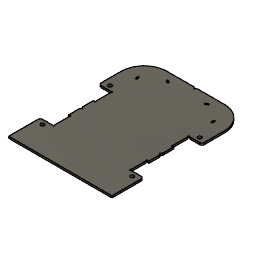
Mice_Sweep (Autodesk Fusion 360 archive; units mm, degrees)
design "下基板"
Autodesk Fusion 360 part; units mm, degrees
sketch "スケッチ1" plane through (0, 0, 0) normal (0, 0, 1) x (1, 0, 0)
  line L0 (-20.044, 48.7765) -> (-21.7923, 49.7477)
  arc A0 (-19.5097, 49.738) -> (-20.044, 48.7765) centre (-19.7768, 49.2572) cw
  arc A1 (-21.7923, 49.7477) -> (-21.2581, 50.7093) centre (-21.5252, 50.2285) cw
  line L1 (-21.2581, 50.7093) -> (-19.5097, 49.738)
  line L2 (31.285, 3.2481) -> (30.335, 3.2481)
  line L3 (-37.765, 3.2481) -> (-38.715, 3.2481)
  arc A2 (-37.215, -32.552) -> (-37.765, -33.102) centre (-37.215, -33.102) cw
  arc A3 (41.285, 37.2481) -> (21.285, 57.2481) centre (21.285, 37.2481) ccw
  line L4 (-38.715, -5.9017) -> (-38.715, -6.7519)
  line L5 (-38.715, 3.2481) -> (-38.715, -5.9017)
  line L6 (-37.765, -33.102) -> (-46.715, -33.102)
  line L7 (31.285, -5.9017) -> (31.285, 3.2481)
  line L8 (-38.715, -6.7519) -> (-37.215, -7.7519)
  arc A4 (29.785, 17.0483) -> (30.335, 17.5983) centre (29.785, 17.5983) cw
  line L9 (-38.715, -18.7519) -> (-37.765, -18.7519)
  line L10 (-37.215, -19.3019) -> (-37.215, -32.552)
  line L11 (29.785, 3.7981) -> (29.785, 17.0483)
  line L12 (-4.715, 57.2481) -> (-28.715, 57.2481)
  line L13 (-3.715, 55.7481) -> (-4.715, 57.2481)
  arc A5 (-46.715, -33.102) -> (-48.715, -35.102) centre (-46.715, -35.102) ccw
  arc A6 (-48.715, 19.5983) -> (-46.715, 17.5983) centre (-46.715, 19.5983) ccw
  line L14 (-48.715, -60.7519) -> (41.285, -60.7519)
  line L15 (-38.715, -8.7519) -> (-38.715, -18.7519)
  line L16 (-48.715, -35.102) -> (-48.715, -40.7519)
  arc A7 (-37.765, 17.5983) -> (-37.215, 17.0483) centre (-37.215, 17.5983) cw
  line L17 (-37.215, -7.7519) -> (-38.715, -8.7519)
  arc A8 (-37.765, -18.7519) -> (-37.215, -19.3019) centre (-37.215, -18.7519) cw
  line L18 (21.285, 57.2481) -> (-2.715, 57.2481)
  line L19 (41.285, -40.7519) -> (41.285, -35.102)
  line L20 (41.285, 19.5983) -> (41.285, 37.2481)
  line L21 (39.285, -33.102) -> (30.335, -33.102)
  arc A9 (39.285, 17.5983) -> (41.285, 19.5983) centre (39.285, 19.5983) ccw
  line L22 (-48.715, -40.7519) -> (-48.715, -60.7519)
  line L23 (31.285, -18.7519) -> (31.285, -8.7519)
  line L24 (-37.215, 17.0483) -> (-37.215, 3.7981)
  line L25 (30.335, 17.5983) -> (39.285, 17.5983)
  line L26 (31.285, -8.7519) -> (29.785, -7.7519)
  line L27 (30.335, -18.7519) -> (31.285, -18.7519)
  line L28 (-46.715, 17.5983) -> (-37.765, 17.5983)
  arc A10 (41.285, -35.102) -> (39.285, -33.102) centre (39.285, -35.102) ccw
  arc A11 (-37.215, 3.7981) -> (-37.765, 3.2481) centre (-37.215, 3.2481) cw
  arc A12 (30.335, 3.2481) -> (29.785, 3.7981) centre (29.785, 3.2481) cw
  arc A13 (30.335, -33.102) -> (29.785, -32.552) centre (29.785, -33.102) cw
  line L29 (41.285, -60.7519) -> (41.285, -40.7519)
  line L30 (29.785, -32.552) -> (29.785, -19.3019)
  line L31 (31.285, -6.7519) -> (31.285, -5.9017)
  line L32 (-48.715, 37.2481) -> (-48.715, 19.5983)
  line L33 (-2.715, 57.2481) -> (-3.715, 55.7481)
  arc A14 (-28.715, 57.2481) -> (-48.715, 37.2481) centre (-28.715, 37.2481) ccw
  line L34 (29.785, -7.7519) -> (31.285, -6.7519)
  arc A15 (29.785, -19.3019) -> (30.335, -18.7519) centre (29.785, -18.7519) cw
  arc A16 (12.6139, 48.7765) -> (12.0797, 49.738) centre (12.3468, 49.2572) cw
  arc A17 (13.828, 50.7093) -> (14.3622, 49.7477) centre (14.0951, 50.2285) cw
  line L35 (12.0797, 49.738) -> (13.828, 50.7093)
  line L36 (14.3622, 49.7477) -> (12.6139, 48.7765)
  arc A18 (-35.9715, 38.427) -> (-37.0548, 38.236) centre (-36.5131, 38.3315) cw
  line L37 (-36.3188, 40.3966) -> (-35.9715, 38.427)
  line L38 (-37.0548, 38.236) -> (-37.4021, 40.2056)
  arc A19 (-37.4021, 40.2056) -> (-36.3188, 40.3966) centre (-36.8604, 40.3011) cw
  line L39 (28.8887, 40.3966) -> (28.5414, 38.427)
  arc A20 (28.5414, 38.427) -> (29.6247, 38.236) centre (29.0831, 38.3315) ccw
  arc A21 (29.972, 40.2056) -> (28.8887, 40.3966) centre (29.4304, 40.3011) ccw
  line L40 (29.6247, 38.236) -> (29.972, 40.2056)
  circle A22 centre (-42.815, 21.5983) radius 1.55
  circle A23 centre (35.385, 21.5983) radius 1.55
  circle A24 centre (35.385, -37.102) radius 1.55
  circle A25 centre (-42.815, -37.102) radius 1.55
  point P0 (-3.715, -7.7519)
  point P1 (-3.715, -7.7519)
extrude "押し出し1" add sketch "スケッチ1" along normal blind 1.6

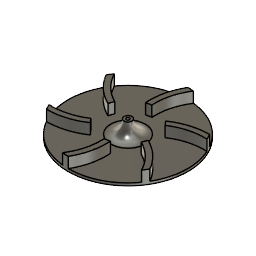
design "吸引ファン1"
Autodesk Fusion 360 part; units mm, degrees
sketch "スケッチ1" plane through (0, 0, 0) normal (0, 0, 1) x (1, 0, 0)
  circle A0 centre (0, 0) radius 22.5
  dimension "d1" = 45
  constraint coincident A0.centre origin
  measures "d1" diameter of A0
extrude "押し出し1" add sketch "スケッチ1" along normal blind 1
sketch "スケッチ2" plane through (0, 0, 1) normal (0, 0, 1) x (-1, 0, 0)
  circle A0 centre (0, 0) radius 22.5
  line L0 (0, 0) -> (0, 22.5)
  line L1 (0, 0) -> (-11.25, 19.4856)
  line L2 (0, 0) -> (-19.4856, 11.25)
  line L3 (0, 0) -> (-22.5, 0)
  line L4 (0, 0) -> (-19.4856, -11.25)
  line L5 (0, 0) -> (-11.25, -19.4856)
  line L6 (0, 0) -> (0, -22.5)
  line L7 (0, 0) -> (11.25, -19.4856)
  line L8 (0, 0) -> (19.4856, -11.25)
  line L9 (0, 0) -> (22.5, 0)
  line L10 (0, 0) -> (19.4856, 11.25)
  line L11 (0, 0) -> (11.25, 19.4856)
  circle A1 centre (0, 22.5) radius 22.5
  circle A2 centre (0, 22.5) radius 20.5
  circle A3 centre (-19.4856, 11.25) radius 20.5
  circle A4 centre (-19.4856, 11.25) radius 22.5
  circle A5 centre (-19.4856, -11.25) radius 20.5
  circle A6 centre (-19.4856, -11.25) radius 22.5
  circle A7 centre (0, -22.5) radius 20.5
  circle A8 centre (0, -22.5) radius 22.5
  circle A9 centre (19.4856, -11.25) radius 20.5
  circle A10 centre (19.4856, -11.25) radius 22.5
  circle A11 centre (19.4856, 11.25) radius 20.5
  circle A12 centre (19.4856, 11.25) radius 22.5
  circle A13 centre (0, 0) radius 10
  dimension "d5" = 360
  dimension "d6" = -2
  dimension "d8" = 360
  constraint coincident A0.centre L0.start
  constraint coincident A0 L0.end
  constraint vertical L0
  constraint coincident L0.end A1.centre
  constraint coincident A0.centre A1
extrude "押し出し2" add sketch "スケッチ2" along normal blind 4 contours A0 A1 A9 | L10 A1 A9 | L10 A2 A10 | L8 A7 A12 | L8 A8 A11 | A0 A7 A12 | A7 A8 A11 A13 | A2 A9 A10 A13 | A0 A4 A11 | L0 A4 A11 | L0 A3 A12 | L6 A5 A10 | L6 A6 A9 | A0 A5 A10 | A5 A6 A9 A13 | A3 A11 A12 A13 | A1 A2 A5 A13 | A3 A4 A7 A13 | A0 A2 A6 | L2 A2 A6 | L2 A1 A5 | A0 A3 A8 | L4 A3 A8 | L4 A4 A7 picked at (14.7277, -6.4258) picked at (12.9288, 9.5417) picked at (1.8397, -15.7623) picked at (-1.799, 15.9675) picked at (-14.7277, 6.4258) picked at (-12.9288, -9.5417)
sketch "スケッチ3" plane through (0, 0, 1) normal (0, 0, 1) x (-1, 0, 0)
  arc A0 (20.5225, 9.2238) -> (8.1325, 5.8192) centre (19.4856, -11.25) ccw
  arc A1 (8.1325, 5.8192) -> (6.7995, 7.3326) centre (0, 0) ccw
  arc A2 (19.4856, 11.25) -> (6.7995, 7.3326) centre (19.4856, -11.25) ccw
  arc A3 (19.4856, 11.25) -> (2.2732, 22.3849) centre (0, 0) ccw
  arc A4 (2.2732, 22.3849) -> (-0.9733, 9.9525) centre (19.4856, 11.25) ccw
  arc A5 (-0.9733, 9.9525) -> (-2.9505, 9.5548) centre (0, 0) ccw
  arc A6 (0, 22.5) -> (-2.9505, 9.5548) centre (19.4856, 11.25) ccw
  arc A7 (0, 22.5) -> (-18.2493, 13.1611) centre (0, 0) ccw
  arc A8 (-18.2493, 13.1611) -> (-9.1058, 4.1333) centre (0, 22.5) ccw
  arc A9 (-9.1058, 4.1333) -> (-9.75, 2.2222) centre (0, 0) ccw
  arc A10 (-19.4856, 11.25) -> (-9.75, 2.2222) centre (0, 22.5) ccw
  arc A11 (-19.4856, 11.25) -> (-20.5225, -9.2238) centre (0, 0) ccw
  arc A12 (-20.5225, -9.2238) -> (-8.1325, -5.8192) centre (-19.4856, 11.25) ccw
  arc A13 (-8.1325, -5.8192) -> (-6.7995, -7.3326) centre (0, 0) ccw
  arc A14 (-19.4856, -11.25) -> (-6.7995, -7.3326) centre (-19.4856, 11.25) ccw
  arc A15 (-19.4856, -11.25) -> (-2.2732, -22.3849) centre (0, 0) ccw
  arc A16 (-2.2732, -22.3849) -> (0.9733, -9.9525) centre (-19.4856, -11.25) ccw
  arc A17 (0.9733, -9.9525) -> (2.9505, -9.5548) centre (0, 0) ccw
  arc A18 (0, -22.5) -> (2.9505, -9.5548) centre (-19.4856, -11.25) ccw
  arc A19 (0, -22.5) -> (18.2493, -13.1611) centre (0, 0) ccw
  arc A20 (18.2493, -13.1611) -> (9.1058, -4.1333) centre (0, -22.5) ccw
  arc A21 (9.1058, -4.1333) -> (9.75, -2.2222) centre (0, 0) ccw
  arc A22 (19.4856, -11.25) -> (9.75, -2.2222) centre (0, -22.5) ccw
  arc A23 (19.4856, -11.25) -> (20.5225, 9.2238) centre (0, 0) ccw
  circle A24 centre (0, 0) radius 1.5
  dimension "d11" = 3
  constraint concentric A1 A24
  measures "d11" diameter of A24
extrude "押し出し3" add sketch "スケッチ3" along normal blind 5 contours A24
sketch "スケッチ4" plane through (0, 0, 6) normal (0, 0, 1) x (-1, 0, 0)
  circle A0 centre (0, 0) radius 1.5
  circle A1 centre (0, 0) radius 0.6
  dimension "d14" = 1.2
  constraint coincident A0.centre A1.centre
  measures "d14" diameter of A1
extrude "押し出し4" cut sketch "スケッチ4" against normal blind 35 contours A1
fillet "フィレット1" radius 5 1 edges at (1.3985, -0.5424, 1)

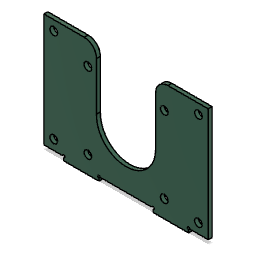
design "モーターマウント"
Autodesk Fusion 360 part; units mm, degrees
sketch "スケッチ1" plane through (0, 0, 0) normal (0, 0, 1) x (1, 0, 0)
  line L0 (25.35, -22.6) -> (25.35, -21)
  line L1 (-11.9915, -0.4526) -> (-11.9915, 20)
  line L2 (12, 0) -> (12, 20)
  arc A0 (-11.9915, 0.4526) -> (8.9572, -7.9855) centre (0, 0) ccw
  arc A1 (8.9572, -7.9855) -> (12, 0) centre (0, 0) ccw
  line L3 (11, -21) -> (-11, -21)
  line L4 (-11, -21) -> (-11, -22.6)
  line L5 (11, -22.6) -> (11, -21)
  line L6 (-25.35, -22.6) -> (-11, -22.6)
  line L7 (11, -22.6) -> (25.35, -22.6)
  line L8 (15.5, 15.5) -> (-15.5, -15.5) construction
  line L9 (-15.5, 15.5) -> (15.5, -15.5) construction
  circle A2 centre (-15.5, 15.5) radius 1.55
  circle A3 centre (-15.5, -15.5) radius 1.55
  circle A4 centre (15.5, -15.5) radius 1.55
  circle A5 centre (15.5, 15.5) radius 1.55
  line L10 (-33.35, 25) -> (-33.35, -21)
  line L11 (-33.35, -21) -> (-25.35, -21)
  line L12 (33.35, 25) -> (33.35, -21)
  line L13 (33.35, -21) -> (25.35, -21)
  line L14 (-33.35, 25) -> (-16.9915, 25)
  line L15 (17, 25) -> (33.35, 25)
  line L16 (-25.35, -21) -> (-25.35, -22.6)
  circle A6 centre (-25.35, -21) radius 0.5
  circle A7 centre (-11, -21) radius 0.5
  circle A8 centre (11, -21) radius 0.5
  circle A9 centre (25.35, -21) radius 0.5
  line L17 (-33.35, 25) -> (-25.35, 25)
  line L18 (-25.35, 25) -> (-25.35, 17)
  line L19 (-33.35, 17) -> (-33.35, 25)
  line L20 (-33.35, -21) -> (-25.35, -21)
  line L21 (-25.35, -21) -> (-25.35, -13)
  line L22 (-33.35, -13) -> (-33.35, -21)
  line L23 (33.35, 25) -> (25.35, 25)
  line L24 (25.35, 25) -> (25.35, 17)
  line L25 (33.35, 17) -> (33.35, 25)
  line L26 (33.35, -21) -> (25.35, -21)
  line L27 (25.35, -21) -> (25.35, -13)
  line L28 (33.35, -13) -> (33.35, -21)
  line L29 (0, 11) -> (0, -6)
  line L30 (-60, 0) -> (-22.7376, 0)
  circle A10 centre (-29.35, 21) radius 1.55
  circle A11 centre (29.35, 21) radius 1.55
  circle A12 centre (-29.35, -17.0232) radius 1.55
  circle A13 centre (29.35, -17.0232) radius 1.55
  arc A14 (-11.9915, 20) -> (-16.9915, 25) centre (-16.9915, 20) ccw
  arc A15 (17, 25) -> (12, 20) centre (17, 20) ccw
  point P0 (82.8077, 25)
  dimension "d5" = 24
  dimension "d11" = 31
  dimension "d12" = 31
  dimension "d13" = 3.1
  dimension "d14" = 3.1
  dimension "d15" = 3.1
  dimension "d16" = 3.1
  dimension "d25" = 14.35
  dimension "d43" = 11
  dimension "d44" = 11
  dimension "d45" = 22.6
  dimension "d46" = 21
  dimension "d49" = 22.6
  dimension "d51" = 33.35
  dimension "d52" = 33.35
  dimension "d53" = 1
  dimension "d54" = 1
  dimension "d55" = 1
  dimension "d56" = 1
  dimension "d57" = 8
  dimension "d58" = 8
  dimension "d59" = 8
  dimension "d60" = 8
  dimension "d61" = 8
  dimension "d62" = 8
  dimension "d63" = 8
  dimension "d64" = 8
  dimension "d83" = 3.1
  dimension "d84" = 3.1
  dimension "d85" = 3.1
  dimension "d86" = 3.1
  dimension "d87" = 14.35
  dimension "d88" = 5
  dimension "d89" = 5
  constraint coincident A0.centre A1.centre
  constraint coincident L1.start A0
  constraint tangent L2 A0
  constraint coincident L1 A0.start
  constraint concentric A0 A1
  constraint perpendicular L3 L4
  constraint parallel L4 L5
  constraint horizontal L3
  constraint coincident L8 A0.centre
  constraint coincident L9 A0.centre
  constraint coincident L9.start A2.centre
  constraint coincident L8.end A3.centre
  constraint coincident L9.end A4.centre
  constraint coincident L8.start A5.centre
  constraint perpendicular L3 L10
  constraint collinear L14 L15
  constraint perpendicular L6 L16
  constraint coincident L11.end L16.start
  constraint coincident L3.end L4.start
  constraint coincident L3.start L5.end
  constraint coincident L0.end L13.end
  constraint horizontal L17
  constraint vertical L18
  constraint vertical L19
  constraint horizontal L20
  constraint vertical L21
  constraint vertical L22
  constraint horizontal L23
  constraint vertical L24
  constraint vertical L25
  constraint horizontal L26
  constraint vertical L27
  constraint vertical L28
  constraint vertical L29
  constraint horizontal L30
  constraint tangent L14 A14
  constraint tangent L1 A14
  constraint tangent L15 A15
  constraint tangent L2 A15
  measures "d5" diameter of A0
  measures "d11" distance of L8.end L9.end
  measures "d12" distance of L9.start L8.end
  measures "d13" diameter of A2
  measures "d14" diameter of A3
  measures "d15" diameter of A4
  measures "d16" diameter of A5
  measures "d25" distance of L0 L5
  measures "d43" distance of A0.centre L4
  measures "d44" distance of L5 A0.centre
  measures "d45" distance of A0.centre L6
  measures "d46" distance of A0.centre L3
  measures "d49" distance of A0.centre L7
  measures "d51" distance of A0.centre L10
  measures "d52" distance of A0.centre L12
  measures "d53" diameter of A6
  measures "d54" diameter of A7
  measures "d55" diameter of A8
  measures "d56" diameter of A9
  measures "d57" distance of L10.start L17.end
  measures "d58" distance of L10.start L19.start
  measures "d59" distance of L10.end L11.end
  measures "d60" distance of L10.end L22.start
  measures "d61" distance of L12.start L23.end
  measures "d62" distance of L12.start L25.start
  measures "d63" distance of L12.end L0.end
  measures "d64" distance of L12.end L28.start
  measures "d83" diameter of A10
  measures "d84" diameter of A11
  measures "d85" diameter of A12
  measures "d86" diameter of A13
  measures "d87" distance of L6.start L4
  measures "d88" radius of A14
  measures "d89" radius of A15
extrude "押し出し1" add sketch "スケッチ1" along normal blind 1.57 contours L0 L1 L2 A0 A1 L3 L4 L5 L6 L7 L10 L11 L12 L13 L14 L15 L16 A6 A7 A8 A9 L17 L19 L20 L22 L23 L25 L26 L28 A14 A15 sketch seen with x (1, 0, 0) y (0, 1, 0) z (0, 0, 1) at (33.35, 22.6, 0) in component "ボード"
component "ボード" placed x (1, 0, 0) y (0, 1, 0) z (0, 0, 1) at (-33.35, -22.6, 0)
equation "d45 = 21 mm + 1.6 mm"
equation "d51 = ( 50.7 / 2 + 8 ) * 1 mm"
equation "d52 = ( 50.7 / 2 + 8 ) * 1 mm"
named bodies: "ボード"

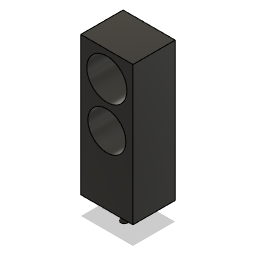
design "センサーホルダー"
Autodesk Fusion 360 part; units mm, degrees
sketch "スケッチ2" plane through (0, 0, 0) normal (0, 0, 1) x (1, 0, 0)
  line L0 (0, 10) -> (0, -10) construction
  line L1 (-10, 0) -> (10, 0) construction
  circle A0 centre (0, 0) radius 2.7
  circle A1 centre (0, 6.35) radius 2.85
  line L2 (0, 10) -> (-3.7, 10)
  line L3 (-3.7, 10) -> (-3.7, -9.7)
  line L4 (-3.7, -9.7) -> (0, -9.7)
  line L5 (0, 10) -> (3.7, 10)
  line L6 (3.7, 10) -> (3.7, -9.7)
  line L7 (3.7, -9.7) -> (0, -9.7)
  dimension "d5" = 20
  dimension "d6" = 20
  dimension "d7" = 5.4
  dimension "d8" = 5.7
  dimension "d9" = 6.35
  dimension "d10" = 3.7
  dimension "d11" = 3.65
  dimension "d12" = 19.7
  constraint vertical L0
  constraint perpendicular L0 L1
  constraint coincident A0.centre origin
  constraint coincident L0 A1.centre
  constraint horizontal L2
  constraint perpendicular L2 L3
  constraint coincident L0 L4.end
  constraint perpendicular L0 L4
  constraint symmetric L0 L2.start L5.start
  constraint symmetric L0 L2.end L5.end
  constraint symmetric L0 L3.end L6.end
  constraint symmetric L0 L4.end L7.end
  measures "d5" distance of L0.start L0.end
  measures "d6" distance of L1.start L1.end
  measures "d7" diameter of A0
  measures "d8" diameter of A1
  measures "d9" distance of A0.centre A1.centre
  measures "d10" distance of L0.start L2.end
  measures "d11" distance of A1.centre L2
  measures "d12" distance of L2.end L3.end
extrude "押し出し2" add sketch "スケッチ2" along normal blind 5 and the other way blind 1
sketch "スケッチ3" plane through (0, -9.7, 0) normal (0, -1, 0) x (1, 0, 0)
  line L0 (-3.7, -1) -> (3.7, -1)
  line L1 (3.7, -1) -> (3.7, 5)
  line L2 (3.7, 5) -> (-3.7, 5)
  line L3 (-3.7, 5) -> (-3.7, -1)
  line L4 (0, 0) -> (0, 3.1) construction
  line L5 (1.0608, 2.55) -> (-1.3, 2.55) construction
  line L6 (1.116, 0.55) -> (-1.3, 0.55) construction
  line L7 (-0.55, 2.55) -> (-0.55, 0.55)
  line L8 (0.55, 0.55) -> (0.55, 2.55)
  arc A0 (0.55, 2.55) -> (-0.55, 2.55) centre (0, 2.55) ccw
  arc A1 (-0.55, 0.55) -> (0.55, 0.55) centre (0, 0.55) ccw
  dimension "d15" = 3.1
  dimension "d24" = 1.1
  constraint coincident L4.start origin
  constraint perpendicular L0 L4
  constraint horizontal L5
  constraint perpendicular L4 L6
  constraint coincident L6 A1.centre
  constraint coincident L4 A1.centre
  constraint coincident L4.start A1
  constraint coincident L5 A0.centre
  constraint coincident L4 A0.centre
  constraint coincident L4.end A0
  constraint coincident L5 L7.start
  constraint coincident L6 L7.end
  constraint coincident L6 L8.start
  constraint coincident L5 L8.end
  measures "d15" distance of L4.start L4.end
  measures "d24" distance of L7 L8
extrude "押し出し3" add sketch "スケッチ3" along normal blind 2.6 contours L7 L8 A0 A1
move_face "面をオフセット1" offset -0.08 1 faces at (0.55, -11.4333, 1.8833)
equation "d9 = ( 5.7 / 2 ) * 1 mm + ( 5.4 / 2 ) * 1 mm + 0.8 mm"
equation "d11 = ( 5.7 / 2 ) * 1 mm + 0.8 mm"
equation "d12 = 0.8 mm + 5.7 mm + 0.8 mm + 5.4 mm + 7 mm"
equation "d15 = 1.1 mm + 2 mm"

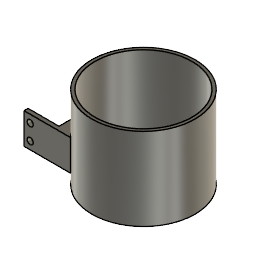
design "吸引筒"
Autodesk Fusion 360 part; units mm, degrees
sketch "スケッチ1" plane through (0, 0, 0) normal (0, 0, 1) x (1, 0, 0)
  circle A0 centre (0, 0) radius 25
  circle A1 centre (0, 0) radius 23.5
  dimension "d1" = 50
  dimension "d2" = 47
  constraint coincident A0.centre A1.centre
  constraint concentric A0 A1
  measures "d1" diameter of A0
  measures "d2" diameter of A1
extrude "押し出し1" add sketch "スケッチ1" along normal blind 40
sketch "スケッチ2" plane through (0, 0, 0) normal (0, 0, -1) x (1, 0, 0)
  circle A0 centre (0, 0) radius 23.5
  circle A1 centre (0, 0) radius 25
  line L0 (0, 0) -> (25, 0)
  line L1 (0, 0) -> (-25, 0)
  line L2 (0, 0) -> (0, -25)
  line L3 (0, 0) -> (0, 25)
  line L4 (-4, 0) -> (-4, -25)
  line L5 (4, 0) -> (4, -25)
  line L6 (0, 4) -> (-25, 4)
  line L7 (0, -4) -> (-25, -4)
  line L8 (4, 0) -> (4, 25)
  line L9 (-4, 0) -> (-4, 25)
  line L10 (0, -4) -> (25, -4)
  line L11 (0, 4) -> (25, 4)
  dimension "d5" = 4
  dimension "d6" = -4
  dimension "d7" = 4
  dimension "d8" = -4
  dimension "d9" = 4
  dimension "d10" = -4
  dimension "d11" = 4
  dimension "d12" = -4
  constraint coincident A0.centre A1.centre
  constraint coincident A1 L0.end
  constraint horizontal L0
  constraint coincident A1 L1.end
  constraint parallel L0 L1
  constraint coincident A1 L2.end
  constraint perpendicular L0 L2
  constraint coincident A1 L3.end
  constraint perpendicular L0 L3
extrude "押し出し2" add sketch "スケッチ2" against normal blind 8 contours A0 L0 L8 L11 | A0 L0 L5 L10 | L0 L2 L5 L10 | L0 L3 L8 L11 | A0 L3 L8 L11 | A0 L2 L5 L10 | L1 L2 L4 L7 | L1 L3 L6 L9 | A0 L3 L6 L9 | A0 L2 L4 L7 | A0 L1 L4 L7 | A0 L1 L6 L9
sketch "スケッチ3" plane through (0, 0, 0) normal (0, 0, -1) x (1, 0, 0)
  arc A0 (23.1571, 4) -> (4, 23.1571) centre (0, 0) ccw
  line L0 (23.1571, 4) -> (4, 4)
  line L1 (4, 4) -> (4, 23.1571)
  line L2 (-4, 23.1571) -> (-4, 4)
  line L3 (-4, 4) -> (-23.1571, 4)
  arc A1 (-4, 23.1571) -> (-23.1571, 4) centre (0, 0) ccw
  line L4 (-23.1571, -4) -> (-4, -4)
  line L5 (-4, -4) -> (-4, -23.1571)
  arc A2 (-23.1571, -4) -> (-4, -23.1571) centre (0, 0) ccw
  line L6 (4, -23.1571) -> (4, -4)
  line L7 (4, -4) -> (23.1571, -4)
  arc A3 (4, -23.1571) -> (23.1571, -4) centre (0, 0) ccw
  circle A4 centre (0, 0) radius 25
  circle A5 centre (0, 0) radius 23.5
  constraint concentric A0 A5
  constraint coincident L4.start A5
extrude "押し出し3" cut sketch "スケッチ3" against normal blind 5 contours L0 L1 L2 L3 L4 L5 L6 L7 A5
sketch "スケッチ4" plane through (0, 0, 8) normal (0, 0, 1) x (-1, 0, 0)
  arc A0 (-23.1571, 4) -> (-23.1571, -4) centre (0, 0) ccw
  line L0 (-23.1571, -4) -> (-4, -4)
  line L1 (-4, -4) -> (-4, -23.1571)
  arc A1 (-4, -23.1571) -> (4, -23.1571) centre (0, 0) ccw
  line L2 (4, -23.1571) -> (4, -4)
  line L3 (4, -4) -> (23.1571, -4)
  arc A2 (23.1571, -4) -> (23.1571, 4) centre (0, 0) ccw
  line L4 (23.1571, 4) -> (4, 4)
  line L5 (4, 4) -> (4, 23.1571)
  arc A3 (4, 23.1571) -> (-4, 23.1571) centre (0, 0) ccw
  line L6 (-4, 23.1571) -> (-4, 4)
  line L7 (-4, 4) -> (-23.1571, 4)
sketch "スケッチ5" plane through (0, 0, 8) normal (0, 0, 1) x (-1, 0, 0)
  circle A0 centre (0, 0) radius 4.25
  circle A1 centre (0, 0) radius 8.5
  dimension "d17" = 8.5
  dimension "d20" = 17
  constraint coincident A0.centre A1.centre
  constraint concentric A0 A1
  measures "d17" diameter of A0
  measures "d20" diameter of A1
extrude "押し出し4" add sketch "スケッチ5" against normal blind 3
sketch "スケッチ6" plane through (0, 0, 8) normal (0, 0, 1) x (-1, 0, 0)
  circle A0 centre (0, 0) radius 4.35
  circle A1 centre (0, 0) radius 5.75
  dimension "d21" = 8.7
  dimension "d22" = 11.5
  constraint coincident A0.centre A1.centre
  measures "d21" diameter of A0
  measures "d22" diameter of A1
extrude "押し出し5" add sketch "スケッチ6" along normal blind 11
fillet "フィレット1" radius 3 1 edges at (5.3609, -2.0793, 8)
sketch "スケッチ7" plane through (0, 0, 8) normal (0, 0, 1) x (-1, 0, 0)
  circle A0 centre (0, 0) radius 4.35
  circle A1 centre (0, 0) radius 3
  constraint coincident A0.centre A1.centre
extrude "押し出し6" cut sketch "スケッチ7" against normal blind 19 contours A1
extrude "押し出し7" cut 1 faces at (-3.8838, 0.2161, 8) along direction (0, 0, -1) blind 2
extrude "押し出し8" cut 1 faces at (-5.2457, 0.5018, 19) along direction (0, 0, -1) blind 5
sketch "スケッチ8" plane through (0, 0, 5) normal (0, 0, -1) x (1, 0, 0)
  circle A0 centre (0, 0) radius 3
  line L0 (-4, -7.5) -> (-4, -23.1571)
  arc A1 (-4, -23.1571) -> (4, -23.1571) centre (0, 0) ccw
  line L1 (4, -23.1571) -> (4, -7.5)
  arc A2 (4, -7.5) -> (7.5, -4) centre (0, 0) ccw
  line L2 (7.5, -4) -> (23.1571, -4)
  arc A3 (23.1571, -4) -> (23.1571, 4) centre (0, 0) ccw
  line L3 (23.1571, 4) -> (7.5, 4)
  arc A4 (7.5, 4) -> (4, 7.5) centre (0, 0) ccw
  line L4 (4, 7.5) -> (4, 23.1571)
  arc A5 (4, 23.1571) -> (-4, 23.1571) centre (0, 0) ccw
  line L5 (-4, 23.1571) -> (-4, 7.5)
  arc A6 (-4, 7.5) -> (-7.5, 4) centre (0, 0) ccw
  line L6 (-7.5, 4) -> (-23.1571, 4)
  arc A7 (-23.1571, 4) -> (-23.1571, -4) centre (0, 0) ccw
  line L7 (-23.1571, -4) -> (-7.5, -4)
  arc A8 (-7.5, -4) -> (-4, -7.5) centre (0, 0) ccw
  line L8 (0, 0) -> (-25, 0)
  line L9 (-25, 0) -> (-25, 15.95)
  circle A9 centre (0, 0) radius 25
  line L10 (-25, 15.95) -> (-19.2509, 15.95)
  line L11 (-25, 15.95) -> (-40, 15.95)
  line L12 (-40, 15.95) -> (-40, 17.95)
  line L13 (-40, 17.95) -> (-17.4011, 17.95)
  line L14 (-25, 0) -> (-25, -15.95)
  line L15 (-25, -15.95) -> (-40, -15.95)
  line L16 (-40, -17.95) -> (-17.4011, -17.95)
  line L17 (-25, -15.95) -> (-19.2509, -15.95)
  line L18 (-40, -15.95) -> (-40, -17.95)
  point P0 (-23.1571, -4)
  dimension "d33" = 15.95
  dimension "d34" = 2
  constraint coincident A0.centre A1.centre
  constraint horizontal L8
  constraint perpendicular L8 L9
  constraint concentric A0 A9
  constraint coincident L8.end A9
  constraint coincident A9 L10.end
  constraint perpendicular L9 L10
  constraint perpendicular L9 L11
  constraint perpendicular L11 L12
  constraint coincident A9 L13.end
  constraint perpendicular L12 L13
  constraint symmetric L6.end L8 P0
  constraint symmetric L9.start L8 L14.start
  constraint symmetric L8 L9.end L14.end
  constraint symmetric L8 L10.end L17.end
  constraint symmetric L8 L11.end L15.end
  constraint symmetric L8 L12.end L16.start
  constraint symmetric L8 L13.end L16.end
  measures "d33" distance of L8.end L9.end
  measures "d34" distance of L11.end L12.end
extrude "押し出し9" add sketch "スケッチ8" against normal blind 15 contours L9 A9 L10 | A9 L14 L17 | A9 L10 L11 L12 L13 | A9 L15 L16 L17 L18
sketch "スケッチ9" plane through (0, 17.95, 0) normal (0, 1, 0) x (-1, 0, 0)
  line L0 (17.4011, 5) -> (40, 5)
  line L1 (40, 5) -> (40, 20)
  line L2 (40, 20) -> (17.4011, 20)
  line L3 (17.4011, 20) -> (17.4011, 5)
  line L4 (40, 5) -> (40, 20)
  line L5 (40, 12.5) -> (37, 12.5)
  line L6 (37, 12.5) -> (37, 5)
  circle A0 centre (37, 8.75) radius 1.5
  line L7 (37, 12.5) -> (37, 20)
  circle A1 centre (37, 16.25) radius 1.5
  dimension "d37" = 3
  dimension "d38" = 3
  constraint coincident L0.end L1.start
  constraint coincident L1.end L2.start
  constraint midpoint L1 L5.start
  constraint perpendicular L1 L5
  constraint coincident L0 L6.end
  constraint perpendicular L0 L6
  constraint midpoint L6 A0.centre
  constraint coincident L2 L7.end
  constraint perpendicular L2 L7
  constraint midpoint L7 A1.centre
  measures "d37" diameter of A0
  measures "d38" diameter of A1
extrude "押し出し10" cut sketch "スケッチ9" against normal blind 52 contours L6 A0 | L6 A0 | L7 A1 | L7 A1
equation "d6 = -d5"
equation "d8 = -d7"
equation "d10 = -d9"
equation "d12 = -d11"
equation "d21 = 8.5 mm + 0.2 mm"
equation "d33 = ( 27.9 / 2 ) * 1 mm + 2 mm"

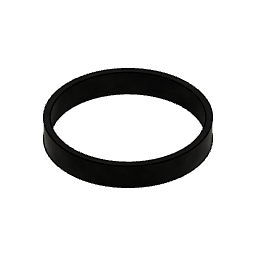
design "タイヤ"
Autodesk Fusion 360 part; units mm, degrees
sketch "スケッチ1" plane through (0, 0, 0) normal (0, 1, 0) x (1, 0, 0)
  circle A0 centre (0, 0) radius 24
  circle A1 centre (0, 0) radius 26
  dimension "d1" = 48
  dimension "d2" = 52
  constraint coincident A0.centre A1.centre
  measures "d1" diameter of A0
  measures "d2" diameter of A1
extrude "押し出し1" add sketch "スケッチ1" along normal blind 8
equation "d2 = 48 mm + 4 mm"

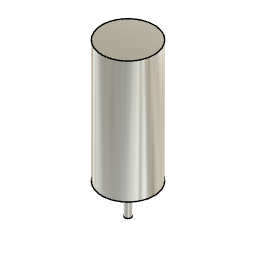
design "吸引モータ"
Autodesk Fusion 360 part; units mm, degrees
sketch "スケッチ1" plane through (0, 0, 0) normal (0, 0, 1) x (1, 0, 0)
  circle A0 centre (0, 0) radius 4.25
  dimension "d1" = 8.5
  constraint coincident A0.centre origin
  measures "d1" diameter of A0
extrude "押し出し1" add sketch "スケッチ1" along normal blind 20
sketch "スケッチ2" plane through (0, 0, 0) normal (0, 0, -1) x (1, 0, 0)
  circle A0 centre (0, 0) radius 4.25
  circle A1 centre (0, 0) radius 0.5
  dimension "d4" = 1
  constraint coincident A0.centre A1.centre
  measures "d4" diameter of A1
extrude "押し出し2" add sketch "スケッチ2" along normal blind 5 contours A1

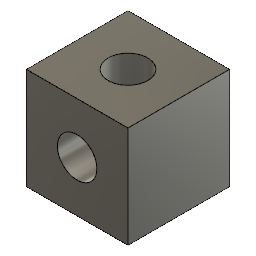
design "角型スペーサ"
Autodesk Fusion 360 part; units mm, degrees
sketch "スケッチ1" plane through (0, 0, 0) normal (0, 0, 1) x (1, 0, 0)
  line L0 (0, 0) -> (8, 0)
  line L1 (8, 0) -> (8, 8)
  line L2 (8, 8) -> (0, 8)
  line L3 (0, 8) -> (0, 0)
  circle A0 centre (4, 4) radius 1.55
  dimension "d1" = 8
  dimension "d4" = 3.1
  constraint horizontal L0
  constraint vertical L1
  constraint horizontal L2
  constraint vertical L3
  constraint coincident L0.start L3.end
  measures "d1" distance of L0.start L2.end
  measures "d4" diameter of A0
extrude "押し出し1" add sketch "スケッチ1" along normal blind 8
sketch "スケッチ2" plane through (0, 0, 0) normal (0, -1, 0) x (1, 0, 0)
  line L0 (0, 0) -> (8, 0)
  line L1 (8, 0) -> (8, 8)
  line L2 (8, 8) -> (0, 8)
  line L3 (0, 8) -> (0, 0)
  circle A0 centre (4, 4) radius 1.55
  dimension "d5" = 3.1
  measures "d5" diameter of A0
extrude "押し出し2" cut sketch "スケッチ2" against normal blind 9 contours A0

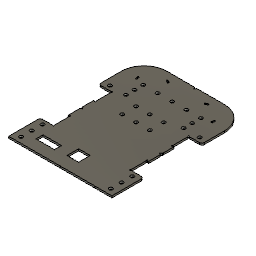
design "上基盤改"
Autodesk Fusion 360 part; units mm, degrees
sketch "スケッチ1" plane through (0, 0, 0) normal (0, 0, 1) x (1, 0, 0)
  line L0 (-16.3289, 51.5283) -> (-18.0773, 52.4996)
  line L1 (-17.543, 53.4612) -> (-15.7947, 52.4899)
  arc A0 (-15.7947, 52.4899) -> (-16.3289, 51.5283) centre (-16.0618, 52.0091) cw
  arc A1 (-18.0773, 52.4996) -> (-17.543, 53.4612) centre (-17.8101, 52.9804) cw
  line L2 (-33.5, 19.8002) -> (-33.5, 6.55)
  arc A2 (33.5, 19.8002) -> (34.05, 20.3502) centre (33.5, 20.3502) cw
  line L3 (34.05, 20.3502) -> (43, 20.3502)
  line L4 (-35, -16) -> (-34.05, -16)
  line L5 (-1, 60) -> (-25, 60)
  line L6 (1, 60) -> (0, 58.5)
  line L7 (25, 60) -> (1, 60)
  line L8 (-43, 20.3502) -> (-34.05, 20.3502)
  arc A3 (45, 40) -> (25, 60) centre (25, 40) ccw
  line L9 (-34.05, 6) -> (-35, 6)
  arc A4 (-33.5, 6.55) -> (-34.05, 6) centre (-33.5, 6) cw
  line L10 (-35, -6) -> (-35, -16)
  arc A5 (-34.05, -16) -> (-33.5, -16.55) centre (-33.5, -16) cw
  arc A6 (-34.05, 20.3502) -> (-33.5, 19.8002) centre (-33.5, 20.3502) cw
  line L11 (45, 22.3502) -> (45, 40)
  line L12 (-45, 40) -> (-45, 22.3502)
  line L13 (-35, -4) -> (-33.5, -5)
  line L14 (0, 58.5) -> (-1, 60)
  line L15 (-35, 6) -> (-35, -3.1498)
  line L16 (-33.5, -5) -> (-35, -6)
  arc A7 (43, 20.3502) -> (45, 22.3502) centre (43, 22.3502) ccw
  arc A8 (-25, 60) -> (-45, 40) centre (-25, 40) ccw
  line L17 (-33.5, -16.55) -> (-33.5, -29.8002)
  line L18 (-45, -32.3502) -> (-45, -38)
  line L19 (-45, -58) -> (45, -58)
  arc A9 (-45, 22.3502) -> (-43, 20.3502) centre (-43, 22.3502) ccw
  line L20 (-34.05, -30.3502) -> (-43, -30.3502)
  arc A10 (-33.5, -29.8002) -> (-34.05, -30.3502) centre (-33.5, -30.3502) cw
  line L21 (-45, -38) -> (-45, -58)
  arc A11 (-43, -30.3502) -> (-45, -32.3502) centre (-43, -32.3502) ccw
  line L22 (45, -58) -> (45, -38)
  line L23 (45, -38) -> (45, -32.3502)
  arc A12 (45, -32.3502) -> (43, -30.3502) centre (43, -32.3502) ccw
  line L24 (43, -30.3502) -> (34.05, -30.3502)
  arc A13 (34.05, -30.3502) -> (33.5, -29.8002) centre (33.5, -30.3502) cw
  line L25 (33.5, -29.8002) -> (33.5, -16.55)
  arc A14 (33.5, -16.55) -> (34.05, -16) centre (33.5, -16) cw
  line L26 (34.05, -16) -> (35, -16)
  line L27 (35, -16) -> (35, -6)
  line L28 (35, -6) -> (33.5, -5)
  line L29 (33.5, -5) -> (35, -4)
  line L30 (35, -4) -> (35, -3.1498)
  line L31 (35, -3.1498) -> (35, 6)
  line L32 (35, 6) -> (34.05, 6)
  arc A15 (34.05, 6) -> (33.5, 6.55) centre (33.5, 6) cw
  line L33 (33.5, 6.55) -> (33.5, 19.8002)
  line L34 (-35, -3.1498) -> (-35, -4)
  arc A16 (16.3289, 51.5283) -> (15.7947, 52.4899) centre (16.0618, 52.0091) cw
  line L35 (15.7947, 52.4899) -> (17.543, 53.4612)
  arc A17 (17.543, 53.4612) -> (18.0773, 52.4996) centre (17.8101, 52.9804) cw
  line L36 (18.0773, 52.4996) -> (16.3289, 51.5283)
  arc A18 (-32.2565, 41.1789) -> (-33.3397, 40.9879) centre (-32.7981, 41.0834) cw
  line L37 (-33.3397, 40.9879) -> (-33.687, 42.9575)
  arc A19 (-33.687, 42.9575) -> (-32.6037, 43.1485) centre (-33.1454, 43.053) cw
  line L38 (-32.6037, 43.1485) -> (-32.2565, 41.1789)
  line L39 (32.6037, 43.1485) -> (32.2565, 41.1789)
  arc A20 (32.2565, 41.1789) -> (33.3397, 40.9879) centre (32.7981, 41.0834) ccw
  line L40 (33.3397, 40.9879) -> (33.687, 42.9575)
  arc A21 (33.687, 42.9575) -> (32.6037, 43.1485) centre (33.1454, 43.053) ccw
  circle A22 centre (-39.1, 24.3502) radius 1.55
  circle A23 centre (39.1, 24.3502) radius 1.55
  circle A24 centre (39.1, -34.3502) radius 1.55
  circle A25 centre (-39.1, -34.3502) radius 1.55
  line L41 (0, -47) -> (5, -47)
  line L42 (0, -47) -> (-5, -47)
  line L43 (-5, -47) -> (-5, -37)
  line L44 (-5, -37) -> (0, -37)
  line L45 (5, -37) -> (0, -37)
  line L46 (5, -47) -> (5, -37)
  line L47 (0, -47) -> (5, -47)
  circle A26 centre (-12, 20) radius 1.5
  circle A27 centre (-12, 8) radius 1.5
  circle A28 centre (12, 20) radius 1.5
  circle A29 centre (12, 8) radius 1.5
  circle A30 centre (0, 20) radius 1.5
  circle A31 centre (0, 8) radius 1.5
  line L48 (-39.1, -34.3502) -> (-39.1, -58)
  line L49 (-39.1, -58) -> (-39.1, -53)
  circle A32 centre (-39.1, -53) radius 1.55
  line L50 (-39.1, -34.3502) -> (-39.1, -43.6752)
  circle A33 centre (-39.1, -43.6752) radius 1.55
  circle A34 centre (39.1, -34.3502) radius 1.55
  circle A35 centre (39.1, -43.6752) radius 1.55
  circle A36 centre (39.1, -53) radius 1.55
  line L51 (0, -58) -> (-30, -58)
  line L52 (0, -58) -> (30, -58)
  line L53 (0, -58) -> (30, -58)
  line L54 (0, -5) -> (-30, -5)
  line L55 (0, -5) -> (30, -5)
  line L56 (-30, -5) -> (-30, -35)
  line L57 (-30, -35) -> (30, -35)
  line L58 (30, -35) -> (30, -5)
  line L59 (-5, -42) -> (-15, -42)
  line L60 (-15, -42) -> (-15, -48)
  line L61 (-15, -48) -> (-25, -48)
  line L62 (-25, -48) -> (-31, -48)
  line L63 (-15, -42) -> (-31, -42)
  line L64 (-31, -42) -> (-31, -48)
  line L65 (39.1, 24.3502) -> (25.1, 24.3502)
  circle A37 centre (25.1, 24.3502) radius 1.5
  line L66 (25.1, 24.3502) -> (25.1, 39.3502)
  circle A38 centre (25.1, 39.3502) radius 1.5
  circle A39 centre (25.1, 31.8502) radius 1.5
  line L67 (25.1, 39.3502) -> (0, 39.3502)
  circle A40 centre (12.55, 39.3502) radius 1.5
  circle A41 centre (0, 39.3502) radius 1.5
  line L68 (0, 58.5) -> (0, 39.3502)
  circle A42 centre (0, 39.3502) radius 1.5
  circle A43 centre (-12.55, 39.3502) radius 1.5
  circle A44 centre (-25.1, 39.3502) radius 1.5
  circle A45 centre (-25.1, 31.8502) radius 1.5
  circle A46 centre (-25.1, 24.3502) radius 1.5
  point P0 (0, 10)
  dimension "d1" = 5
  dimension "d2" = 3.1
  dimension "d3" = 9.325
  dimension "d4" = 3.1
  dimension "d5" = 30
  dimension "d6" = 30
  dimension "d7" = 30
  dimension "d12" = 14
  dimension "d13" = 3
  dimension "d14" = 15
  dimension "d15" = 3
  dimension "d16" = 3
  dimension "d17" = 3
  dimension "d18" = 3
  constraint coincident A25.centre L48.start
  constraint coincident L19 L48.end
  constraint perpendicular L19 L48
  constraint perpendicular L19 L49
  constraint coincident L49.end A32.centre
  constraint parallel L48 L50
  constraint coincident L50.end A33.centre
  constraint midpoint L19 L51.start
  constraint coincident L19 L52.end
  constraint horizontal L54
  constraint parallel L54 L55
  constraint perpendicular L54 L56
  constraint perpendicular L55 L58
  constraint midpoint L43 L59.start
  constraint perpendicular L43 L59
  constraint perpendicular L59 L60
  constraint perpendicular L60 L61
  constraint perpendicular L60 L62
  constraint perpendicular L60 L63
  constraint perpendicular L62 L64
  constraint coincident A23.centre L65.start
  constraint horizontal L65
  constraint coincident L65.end A37.centre
  constraint perpendicular L65 L66
  constraint coincident L66.end A38.centre
  constraint midpoint L66 A39.centre
  constraint perpendicular L66 L67
  constraint midpoint L67 A40.centre
  constraint coincident L67.end A41.centre
  constraint perpendicular L67 L68
  constraint symmetric A37 L68 A46
  constraint symmetric A38 L68 A44
  constraint symmetric A39 L68 A45
  constraint symmetric A40 L68 A43
  constraint symmetric A41 L68 A42
  measures "d1" distance of L48.end L49.end
  measures "d2" diameter of A32
  measures "d3" distance of A25.centre L50.end
  measures "d4" diameter of A33
  measures "d5" distance of L51.start L51.end
  measures "d6" distance of L54.start L54.end
  measures "d7" distance of L54.start L55.end
  measures "d12" distance of A23.centre L65.end
  measures "d13" diameter of A37
  measures "d14" distance of L65.end L66.end
  measures "d15" diameter of A38
  measures "d16" diameter of A39
  measures "d17" diameter of A40
  measures "d18" diameter of A41
extrude "押し出し1" add sketch "スケッチ1" along normal blind 1.6 contours L2 A2 L3 L4 L5 L6 L7 L8 A3 L9 A4 L10 A5 A6 L11 L12 L13 L14 L15 L16 A7 A8 L17 L18 L19 A9 L20 A10 L21 A11 L22 L23 A12 L24 A13 L25 A14 L26 L27 L28 L29 L30 L31 L32 A15 L33 L34 L51 L52 L53 | L54 L55 L56 L57 L58 | L60 L61 L62 L63 L64 | L65 A37 L66 | L65 A37 L66 | L66 A39 | L66 A39 | L66 A38 L67 | L66 A38 L67 | L67 A41 L68 A42 | L67 A41 L68 A42 | L67 A40 | L67 A40 | A43 | A44 | A45 | A46
extrude "押し出し2" cut sketch "スケッチ1" along normal blind 46 contours L60 L61 L62 L63 L64
extrude "押し出し3" cut sketch "スケッチ1" along normal blind 60 contours L65 A37 L66 | L65 A37 L66 | L66 A39 | L66 A39 | L66 A38 L67 | L66 A38 L67 | L67 A41 L68 A42 | L67 A40 | L67 A40 | A43 | A44 | A45 | A46 picked at (-0.8426, 38.8166)
extrude "押し出し4" cut sketch "スケッチ1" along normal blind 12 contours L67 A41 L68 A42 picked at (0.9949, 39.4213)

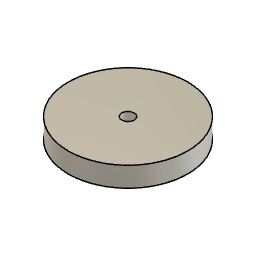
design "ホイール"
Autodesk Fusion 360 part; units mm, degrees
sketch "スケッチ1" plane through (0, 0, 0) normal (0, 1, 0) x (1, 0, 0)
  circle A0 centre (0, 0) radius 2.5
  circle A1 centre (0, 0) radius 24
  dimension "d1" = 5
  dimension "d2" = 48
  constraint coincident A0.centre A1.centre
  measures "d1" diameter of A0
  measures "d2" diameter of A1
extrude "押し出し1" add sketch "スケッチ1" along normal blind 8
